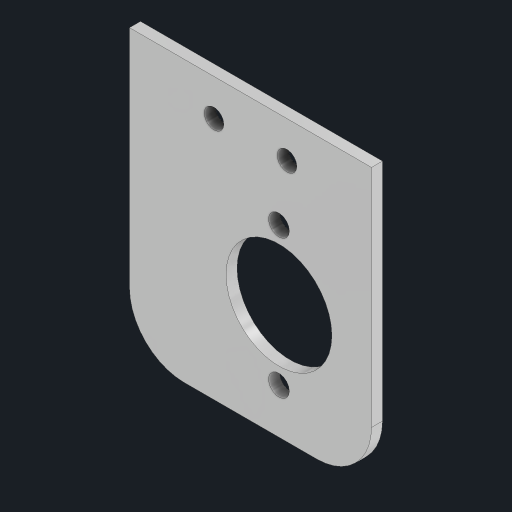
# Autodesk Inventor part: Chapa motor
Saved by Autodesk Inventor 2026.1 (Build 301233020, 233B)
## iProperties
Created: 2025-01-07
Part Number: Chapa motor
Material: Alumínio
Document SubType Name: Modeling
Designer: Cliente
Density: 2.7 g/cm^3
Appearance: Acetinado
Mass: 34.2734 g
Surface Area: 97.6448 cm^2
Volume: 12.6938 cm^3
Author: Cliente
Autodesk Inventor part; units mm, degrees
ref_plane "YZ Plane" through (0, 0, 0) normal (1, 0, 0) x (0, 1, 0)
ref_plane "XZ Plane" through (0, 0, 0) normal (0, 1, 0) x (-1, 0, 0)
ref_plane "XY Plane" through (0, 0, 0) normal (0, 0, 1) x (1, 0, 0)
sketch "Esboço1" plane through (0, 0, 0) normal (0, 0, 1) x (1, 0, 0)
  circle A0 centre (28.5665, -19) radius 2.85 projected
  circle A1 centre (28.5665, 19) radius 2.85 projected
  circle A2 centre (19.0665, 16.4545) radius 3.7 projected
  circle A3 centre (19.0665, -16.4545) radius 3.7 projected
  circle A4 centre (47.5665, 0) radius 3.7 projected
  circle A5 centre (28.5665, 0) radius 14.3 projected
  circle A6 centre (28.5665, 0) radius 25.35 projected
  circle A7 centre (20.7665, 0) radius 3.15 projected
  circle A8 centre (30.7665, 35.35) radius 2.5 projected
  circle A9 centre (10.7665, 35.35) radius 2.5 projected
  line L0 (40.2665, 45.35) -> (35.5665, 45.35) projected
  line L1 (35.5665, 45.35) -> (33.7665, 43.55) projected
  line L2 (33.7665, 43.55) -> (36.2665, 43.55) projected
  line L3 (36.2665, 43.55) -> (36.2665, 41.8399) projected
  line L4 (36.2665, 41.8399) -> (33.7765, 39.35) projected
  line L5 (33.7765, 39.35) -> (27.7564, 39.35) projected
  line L6 (27.7564, 39.35) -> (25.2665, 41.8399) projected
  line L7 (25.2665, 41.8399) -> (25.2665, 43.55) projected
  line L8 (25.2665, 43.55) -> (27.7665, 43.55) projected
  line L9 (27.7665, 43.55) -> (25.9665, 45.35) projected
  line L10 (25.9665, 45.35) -> (15.5665, 45.35) projected
  line L11 (15.5665, 45.35) -> (13.7665, 43.55) projected
  line L12 (13.7665, 43.55) -> (16.2665, 43.55) projected
  line L13 (16.2665, 43.55) -> (16.2665, 41.8399) projected
  line L14 (16.2665, 41.8399) -> (13.7765, 39.35) projected
  line L15 (13.7765, 39.35) -> (7.7564, 39.35) projected
  line L16 (7.7564, 39.35) -> (5.2665, 41.8399) projected
  line L17 (5.2665, 41.8399) -> (5.2665, 43.55) projected
  line L18 (5.2665, 43.55) -> (7.7665, 43.55) projected
  line L19 (7.7665, 43.55) -> (5.9665, 45.35) projected
  line L20 (5.9665, 45.35) -> (1.2665, 45.35) projected
  arc A10 (1.2665, 45.35) -> (0.7665, 44.85) centre (1.2665, 44.85) ccw projected
  line L21 (0.7665, 44.85) -> (0.7665, 40.15) projected
  line L22 (0.7665, 40.15) -> (2.5665, 38.35) projected
  line L23 (2.5665, 38.35) -> (2.5665, 40.85) projected
  line L24 (2.5665, 40.85) -> (4.2765, 40.85) projected
  line L25 (4.2765, 40.85) -> (6.7665, 38.3601) projected
  line L26 (6.7665, 38.3601) -> (6.7665, 32.3399) projected
  line L27 (6.7665, 32.3399) -> (4.2765, 29.85) projected
  line L28 (4.2765, 29.85) -> (2.5665, 29.85) projected
  line L29 (2.5665, 29.85) -> (2.5665, 32.35) projected
  line L30 (2.5665, 32.35) -> (0.7665, 30.55) projected
  line L31 (0.7665, 30.55) -> (0.7665, 25.85) projected
  arc A11 (0.7665, 25.85) -> (1.2665, 25.35) centre (1.2665, 25.85) ccw projected
  line L32 (1.2665, 25.35) -> (5.9665, 25.35) projected
  line L33 (5.9665, 25.35) -> (7.7665, 27.15) projected
  line L34 (7.7665, 27.15) -> (5.2665, 27.15) projected
  line L35 (5.2665, 27.15) -> (5.2665, 28.8601) projected
  line L36 (5.2665, 28.8601) -> (7.7564, 31.35) projected
  line L37 (7.7564, 31.35) -> (13.7765, 31.35) projected
  line L38 (13.7765, 31.35) -> (16.2665, 28.8601) projected
  line L39 (16.2665, 28.8601) -> (16.2665, 27.15) projected
  line L40 (16.2665, 27.15) -> (13.7665, 27.15) projected
  line L41 (13.7665, 27.15) -> (15.5665, 25.35) projected
  line L42 (15.5665, 25.35) -> (25.9665, 25.35) projected
  line L43 (25.9665, 25.35) -> (27.7665, 27.15) projected
  line L44 (27.7665, 27.15) -> (25.2665, 27.15) projected
  line L45 (25.2665, 27.15) -> (25.2665, 28.8601) projected
  line L46 (25.2665, 28.8601) -> (27.7564, 31.35) projected
  line L47 (27.7564, 31.35) -> (33.7765, 31.35) projected
  line L48 (33.7765, 31.35) -> (36.2665, 28.8601) projected
  line L49 (36.2665, 28.8601) -> (36.2665, 27.15) projected
  line L50 (36.2665, 27.15) -> (33.7665, 27.15) projected
  line L51 (33.7665, 27.15) -> (35.5665, 25.35) projected
  line L52 (35.5665, 25.35) -> (40.2665, 25.35) projected
  arc A12 (40.2665, 25.35) -> (40.7665, 25.85) centre (40.2665, 25.85) ccw projected
  line L53 (40.7665, 25.85) -> (40.7665, 30.55) projected
  line L54 (40.7665, 30.55) -> (38.9665, 32.35) projected
  line L55 (38.9665, 32.35) -> (38.9665, 29.85) projected
  line L56 (38.9665, 29.85) -> (37.2564, 29.85) projected
  line L57 (37.2564, 29.85) -> (34.7665, 32.3399) projected
  line L58 (34.7665, 32.3399) -> (34.7665, 38.3601) projected
  line L59 (34.7665, 38.3601) -> (37.2564, 40.85) projected
  line L60 (37.2564, 40.85) -> (38.9665, 40.85) projected
  line L61 (38.9665, 40.85) -> (38.9665, 38.35) projected
  line L62 (38.9665, 38.35) -> (40.7665, 40.15) projected
  line L63 (40.7665, 40.15) -> (40.7665, 44.85) projected
  arc A13 (40.7665, 44.85) -> (40.2665, 45.35) centre (40.2665, 44.85) ccw projected
  circle A14 centre (30.7665, 35.35) radius 2.5 projected
  circle A15 centre (10.7665, 35.35) radius 2.5 projected
  line L64 (23.8665, 27.15) -> (17.6665, 27.15) projected
  line L65 (17.6665, 27.15) -> (17.6665, 29.4399) projected
  line L66 (17.6665, 29.4399) -> (14.7665, 32.3399) projected
  line L67 (14.7665, 32.3399) -> (14.7665, 38.3601) projected
  line L68 (14.7665, 38.3601) -> (17.6665, 41.2601) projected
  line L69 (17.6665, 41.2601) -> (17.6665, 43.55) projected
  line L70 (17.6665, 43.55) -> (23.8665, 43.55) projected
  line L71 (23.8665, 43.55) -> (23.8665, 41.2601) projected
  line L72 (23.8665, 41.2601) -> (26.7665, 38.3601) projected
  line L73 (26.7665, 38.3601) -> (26.7665, 32.3399) projected
  line L74 (26.7665, 32.3399) -> (23.8665, 29.4399) projected
  line L75 (23.8665, 29.4399) -> (23.8665, 27.15) projected
  circle A16 centre (20.7665, 0) radius 33.15
  line L76 (-12.3835, 0) -> (-12.3835, 45.35)
  line L77 (53.9165, 0) -> (53.9165, 45.35)
  line L78 (53.9165, 33.15) -> (-12.3835, 33.15)
  line L79 (-12.3835, 33.15) -> (-12.3835, -16.35)
  line L80 (53.9165, -16.35) -> (53.9165, 33.15)
  line L81 (53.9165, 33.15) -> (-12.3835, -33.15) construction
  line L82 (-12.3835, 33.15) -> (53.9165, -33.15) construction
  line L83 (-12.3835, 45.35) -> (53.9165, 45.35)
  circle A17 centre (10.7665, 35.35) radius 2.7
  circle A18 centre (30.7665, 35.35) radius 2.7
  circle A19 centre (28.5665, 0) radius 14.5
  line L84 (53.9165, -33.15) -> (-12.3835, -33.15)
  line L85 (28.5665, -25.35) -> (28.5665, -31.35)
  line L86 (28.5665, -31.35) -> (38.9165, -31.35)
  line L87 (28.5665, -31.35) -> (2.6165, -31.35)
  arc A20 (38.9165, -31.35) -> (53.9165, -16.35) centre (38.9165, -16.35) ccw
  arc A21 (-12.3835, -16.35) -> (2.6165, -31.35) centre (2.6165, -16.35) ccw
  point P0 (0, 0)
  point P1 (1.2665, 45.35)
  point P2 (40.2665, 45.35)
  point P3 (35.3631, 29.7634)
  point P4 (31.5414, 31.35)
  point P5 (9.9915, 31.35)
  point P6 (6.1698, 29.7634)
  point P7 (6.7665, 33.15)
  point P8 (9.2012, 33.15)
  point P9 (12.3317, 33.15)
  point P10 (14.7665, 33.15)
  point P11 (26.7665, 33.15)
  point P12 (29.2012, 33.15)
  point P13 (32.3317, 33.15)
  point P14 (34.7665, 33.15)
  point P15 (-12.3835, -31.35)
  point P16 (9.9915, -31.35)
  point P17 (-12.3835, 0)
  point P18 (0.7665, 26.4371)
  point P19 (40.7665, 26.4371)
  point P20 (31.5414, -31.35)
  point P21 (53.9165, 33.15)
  point P22 (15.5665, 45.35)
  point P23 (5.9665, 45.35)
  point P24 (35.5665, 45.35)
  point P25 (25.9665, 45.35)
  point P26 (20.7665, 33.15)
  point P27 (53.9165, 0)
  point P28 (26.7665, 32.6025)
  point P29 (14.7665, 32.6025)
  point P30 (53.9165, 0)
  point P31 (-3.4123, 39.9724)
  point P32 (-12.1877, 39.9724)
  point P33 (-11.896, 40.264)
  point P34 (-3.704, 40.264)
  point P35 (-21.8, 37.1627)
  point P36 (-15.5308, 39.35)
  point P37 (-14.5758, 39.5642)
  point P38 (-1.0242, 39.5642)
  point P39 (6.2, 37.1627)
  point P40 (-0.0692, 39.35)
  point P41 (7.7, 29.3031)
  point P42 (-23.3, 29.3031)
  point P43 (12.0813, 26.5265)
  point P44 (-27.6813, 26.5265)
  point P45 (-2.4281, 32.7119)
  point P46 (-13.1719, 32.7119)
  point P47 (-13.6101, 33.15)
  point P48 (-1.9899, 33.15)
  dimension "d1" = 5.4
  dimension "d2" = 5.4
  dimension "d3" = 0.2
  dimension "d6" = 6
  dimension "d7" = 15
  constraints: 24 end point, 6 point on circle, 6 vertical, 5 centre point, 5 point on line, 5 tangent, 4 horizontal, 3 coincident, 2 midpoint, 2 perpendicular, 1 equal radius, 1 horizontal alignment, 1 parallel, 1 vertical alignment, 5 other
  measures "d1" diameter of A17
  measures "d2" diameter of A18
  measures "d3" radial gap between concentric circles of A5 A19
  measures "d6" distance of L85.start L85.end
  measures "d7" radius of A20
extrude "Extrusão1" add sketch "Esboço1" along normal blind 3 contours A2 | A3 | A4 | A6 | A16 L86 L85 A6 | A6 L85 L87 A16 L31 A11 L32 L33 L34 L35 L36 L37 L38 L39 L40 L41 L42 L43 L44 L45 L46 L47 L48 L49 L50 L51 L52 A12 L53 | L80 A20 L86 A16 | A16 L53 L54 L55 L56 L57 L58 L78 L77 | A16 L48 L47 L73 L78 A18 L58 L57 L56 L55 L54 L53 | L53 A12 L52 L51 L50 L49 L48 A16 | L78 L58 L59 L60 L61 L62 L63 A13 L83 L77 | A16 L47 L48 | L78 A18 L73 L72 L71 L70 L69 L68 L67 A17 L26 L25 L24 L23 L22 L21 A10 L20 L19 L18 L17 L16 L15 L14 L13 L12 L11 L10 L9 L8 L7 L6 L5 L4 L3 L2 L1 L0 A13 L63 L62 L61 L60 L59 L58 | L87 A21 L79 A16 | L47 L46 L45 L44 L43 L42 L41 L40 L39 L38 L37 A16 L67 L66 L65 L64 L75 L74 L73 | L76 L78 L26 L27 L28 L29 L30 L31 A16 | A16 L78 L73 | L73 L74 L75 L64 L65 L66 L67 A16 | L1 L2 L3 L4 L5 L6 L7 L8 L9 L83 | A16 L36 L35 L34 L33 L32 A11 L31 | L31 L30 L29 L28 L27 L26 L78 A17 L67 A16 L37 L36 | L76 L83 A10 L21 L22 L23 L24 L25 L26 L78 | L78 L67 L68 L69 L70 L71 L72 L73 | A16 L67 L78 | L36 L37 A16 | L11 L12 L13 L14 L15 L16 L17 L18 L19 L83
